Autodesk Fusion 360 part; units mm, degrees
(part 3 of 3)
sketch "草图6 (16)" plane through (0, 0, 148) normal (0, 0, 1) x (1, 0, 0) in component "19_CPU_LONGITUDINAL_BOARD_RAIL_243_84mm"
  circle A0 centre (298.45, 6.35) radius 4
extrude "Board hole 9 unchanged" add sketch "草图6 (16)" along normal blind 10 bodies 35 in component "19_CPU_LONGITUDINAL_BOARD_RAIL_243_84mm"
ref_plane "工作平面7" through (0, 0, 153.1) normal (0, 0, 1) x (1, 0, 0) in component "19_CPU_LONGITUDINAL_BOARD_RAIL_243_84mm"
sketch "草图7 (13)" plane through (0, 0, 153.1) normal (0, 0, 1) x (1, 0, 0) in component "19_CPU_LONGITUDINAL_BOARD_RAIL_243_84mm"
  circle A0 centre (298.45, 6.35) radius 2.35
extrude "Trial M3 H4.5 OD5 board insert 9" cut sketch "草图7 (13)" along normal blind 4.9 bodies 35 in component "19_CPU_LONGITUDINAL_BOARD_RAIL_243_84mm"
ref_plane "工作平面8" through (0, 0, 140) normal (0, 0, 1) x (1, 0, 0) in component "19_CPU_LONGITUDINAL_BOARD_RAIL_243_84mm"
sketch "草图8 (11)" plane through (0, 0, 140) normal (0, 0, 1) x (1, 0, 0) in component "19_CPU_LONGITUDINAL_BOARD_RAIL_243_84mm"
  circle A0 centre (294, 20) radius 1.7
extrude "M3 side rail mounting clearance'" cut sketch "草图8 (11)" along normal blind 8 bodies 35 in component "19_CPU_LONGITUDINAL_BOARD_RAIL_243_84mm"
ref_plane "工作平面5" through (0, 0, 133.5) normal (0, 0, 1) x (1, 0, 0) in component "16_CPU_VERTICAL_SIDE_FLUSH_TO_BEAM"
sketch "草图5 (20)" plane through (0, 0, 133.5) normal (0, 0, 1) x (1, 0, 0) in component "16_CPU_VERTICAL_SIDE_FLUSH_TO_BEAM"
  circle A0 centre (294, 20) radius 2.35
extrude "Trial short insert for side rail anchor'" cut sketch "草图5 (20)" along normal blind 6.5 bodies 29 in component "16_CPU_VERTICAL_SIDE_FLUSH_TO_BEAM"
ref_plane "工作平面9" through (0, 0, 140) normal (0, 0, 1) x (1, 0, 0) in component "19_CPU_LONGITUDINAL_BOARD_RAIL_243_84mm"
sketch "草图9 (9)" plane through (0, 0, 140) normal (0, 0, 1) x (1, 0, 0) in component "19_CPU_LONGITUDINAL_BOARD_RAIL_243_84mm"
  circle A0 centre (294, 225) radius 1.7
extrude "M3 side rail mounting clearance (1)'" cut sketch "草图9 (9)" along normal blind 8 bodies 35 in component "19_CPU_LONGITUDINAL_BOARD_RAIL_243_84mm"
ref_plane "工作平面6" through (0, 0, 133.5) normal (0, 0, 1) x (1, 0, 0) in component "16_CPU_VERTICAL_SIDE_FLUSH_TO_BEAM"
sketch "草图6 (17)" plane through (0, 0, 133.5) normal (0, 0, 1) x (1, 0, 0) in component "16_CPU_VERTICAL_SIDE_FLUSH_TO_BEAM"
  circle A0 centre (294, 225) radius 2.35
extrude "Trial short insert for side rail anchor (1)'" cut sketch "草图6 (17)" along normal blind 6.5 bodies 29 in component "16_CPU_VERTICAL_SIDE_FLUSH_TO_BEAM"
ref_plane "工作平面1" through (0, 0, 148) normal (0, 0, 1) x (1, 0, 0) in component "20_GPU_INDEPENDENT_FAN_SHOE_140mm"
sketch "草图1 (32)" plane through (0, 0, 148) normal (0, 0, 1) x (1, 0, 0) in component "20_GPU_INDEPENDENT_FAN_SHOE_140mm"
  line L0 (12.4, -25) -> (152.4, -25)
  line L1 (152.4, -25) -> (152.4, -19)
  line L2 (152.4, -19) -> (12.4, -19)
  line L3 (12.4, -19) -> (12.4, -25)
extrude "140 mm fan shoe" add sketch "草图1 (32)" along normal blind 12 separate body makes body 36 in component "20_GPU_INDEPENDENT_FAN_SHOE_140mm"
ref_plane "工作平面2" through (0, 0, 140) normal (0, 0, 1) x (1, 0, 0) in component "20_GPU_INDEPENDENT_FAN_SHOE_140mm"
sketch "草图2 (23)" plane through (0, 0, 140) normal (0, 0, 1) x (1, 0, 0) in component "20_GPU_INDEPENDENT_FAN_SHOE_140mm"
  line L0 (45, -19) -> (55, -19)
  line L1 (55, -19) -> (55, 6)
  line L2 (55, 6) -> (45, 6)
  line L3 (45, 6) -> (45, -19)
extrude "Deep short arm bears on front frame" add sketch "草图2 (23)" along normal blind 14 bodies 36 in component "20_GPU_INDEPENDENT_FAN_SHOE_140mm"
ref_plane "工作平面3" through (0, 0, 140) normal (0, 0, 1) x (1, 0, 0) in component "20_GPU_INDEPENDENT_FAN_SHOE_140mm"
sketch "草图3 (22)" plane through (0, 0, 140) normal (0, 0, 1) x (1, 0, 0) in component "20_GPU_INDEPENDENT_FAN_SHOE_140mm"
  circle A0 centre (50, 2) radius 1.7
extrude "M3 shoe mounting screw clearance" cut sketch "草图3 (22)" along normal blind 14 bodies 36 in component "20_GPU_INDEPENDENT_FAN_SHOE_140mm"
ref_plane "工作平面7" through (0, 0, 133.5) normal (0, 0, 1) x (1, 0, 0) in component "12_front_PCI_SUPPORT_FRAME"
sketch "草图7 (14)" plane through (0, 0, 133.5) normal (0, 0, 1) x (1, 0, 0) in component "12_front_PCI_SUPPORT_FRAME"
  circle A0 centre (50, 2) radius 2.35
extrude "Trial short insert for fan shoe anchor" cut sketch "草图7 (14)" along normal blind 6.5 bodies 24 in component "12_front_PCI_SUPPORT_FRAME"
ref_plane "工作平面4" through (0, 0, 140) normal (0, 0, 1) x (1, 0, 0) in component "20_GPU_INDEPENDENT_FAN_SHOE_140mm"
sketch "草图4 (22)" plane through (0, 0, 140) normal (0, 0, 1) x (1, 0, 0) in component "20_GPU_INDEPENDENT_FAN_SHOE_140mm"
  line L0 (105, -19) -> (115, -19)
  line L1 (115, -19) -> (115, 6)
  line L2 (115, 6) -> (105, 6)
  line L3 (105, 6) -> (105, -19)
extrude "Deep short arm bears on front frame (1)" add sketch "草图4 (22)" along normal blind 14 bodies 36 in component "20_GPU_INDEPENDENT_FAN_SHOE_140mm"
ref_plane "工作平面5" through (0, 0, 140) normal (0, 0, 1) x (1, 0, 0) in component "20_GPU_INDEPENDENT_FAN_SHOE_140mm"
sketch "草图5 (21)" plane through (0, 0, 140) normal (0, 0, 1) x (1, 0, 0) in component "20_GPU_INDEPENDENT_FAN_SHOE_140mm"
  circle A0 centre (110, 2) radius 1.7
extrude "M3 shoe mounting screw clearance (1)" cut sketch "草图5 (21)" along normal blind 14 bodies 36 in component "20_GPU_INDEPENDENT_FAN_SHOE_140mm"
ref_plane "工作平面8" through (0, 0, 133.5) normal (0, 0, 1) x (1, 0, 0) in component "12_front_PCI_SUPPORT_FRAME"
sketch "草图8 (12)" plane through (0, 0, 133.5) normal (0, 0, 1) x (1, 0, 0) in component "12_front_PCI_SUPPORT_FRAME"
  circle A0 centre (110, 2) radius 2.35
extrude "Trial short insert for fan shoe anchor (1)" cut sketch "草图8 (12)" along normal blind 6.5 bodies 24 in component "12_front_PCI_SUPPORT_FRAME"
ref_plane "工作平面1" through (0, 0, 148) normal (0, 0, 1) x (1, 0, 0) in component "20_CPU_INDEPENDENT_FAN_SHOE_140mm"
sketch "草图1 (33)" plane through (0, 0, 148) normal (0, 0, 1) x (1, 0, 0) in component "20_CPU_INDEPENDENT_FAN_SHOE_140mm"
  line L0 (156.4, -25) -> (296.4, -25)
  line L1 (296.4, -25) -> (296.4, -19)
  line L2 (296.4, -19) -> (156.4, -19)
  line L3 (156.4, -19) -> (156.4, -25)
extrude "140 mm fan shoe'" add sketch "草图1 (33)" along normal blind 12 separate body makes body 37 in component "20_CPU_INDEPENDENT_FAN_SHOE_140mm"
ref_plane "工作平面2" through (0, 0, 140) normal (0, 0, 1) x (1, 0, 0) in component "20_CPU_INDEPENDENT_FAN_SHOE_140mm"
sketch "草图2 (24)" plane through (0, 0, 140) normal (0, 0, 1) x (1, 0, 0) in component "20_CPU_INDEPENDENT_FAN_SHOE_140mm"
  line L0 (195, -19) -> (205, -19)
  line L1 (205, -19) -> (205, 6)
  line L2 (205, 6) -> (195, 6)
  line L3 (195, 6) -> (195, -19)
extrude "Deep short arm bears on front frame'" add sketch "草图2 (24)" along normal blind 14 bodies 37 in component "20_CPU_INDEPENDENT_FAN_SHOE_140mm"
ref_plane "工作平面3" through (0, 0, 140) normal (0, 0, 1) x (1, 0, 0) in component "20_CPU_INDEPENDENT_FAN_SHOE_140mm"
sketch "草图3 (23)" plane through (0, 0, 140) normal (0, 0, 1) x (1, 0, 0) in component "20_CPU_INDEPENDENT_FAN_SHOE_140mm"
  circle A0 centre (200, 2) radius 1.7
extrude "M3 shoe mounting screw clearance'" cut sketch "草图3 (23)" along normal blind 14 bodies 37 in component "20_CPU_INDEPENDENT_FAN_SHOE_140mm"
ref_plane "工作平面6" through (0, 0, 133.5) normal (0, 0, 1) x (1, 0, 0) in component "12_front_CPU_SUPPORT_FRAME"
sketch "草图6 (18)" plane through (0, 0, 133.5) normal (0, 0, 1) x (1, 0, 0) in component "12_front_CPU_SUPPORT_FRAME"
  circle A0 centre (200, 2) radius 2.35
extrude "Trial short insert for fan shoe anchor'" cut sketch "草图6 (18)" along normal blind 6.5 bodies 25 in component "12_front_CPU_SUPPORT_FRAME"
ref_plane "工作平面4" through (0, 0, 140) normal (0, 0, 1) x (1, 0, 0) in component "20_CPU_INDEPENDENT_FAN_SHOE_140mm"
sketch "草图4 (23)" plane through (0, 0, 140) normal (0, 0, 1) x (1, 0, 0) in component "20_CPU_INDEPENDENT_FAN_SHOE_140mm"
  line L0 (260, -19) -> (270, -19)
  line L1 (270, -19) -> (270, 6)
  line L2 (270, 6) -> (260, 6)
  line L3 (260, 6) -> (260, -19)
extrude "Deep short arm bears on front frame (1)'" add sketch "草图4 (23)" along normal blind 14 bodies 37 in component "20_CPU_INDEPENDENT_FAN_SHOE_140mm"
ref_plane "工作平面5" through (0, 0, 140) normal (0, 0, 1) x (1, 0, 0) in component "20_CPU_INDEPENDENT_FAN_SHOE_140mm"
sketch "草图5 (22)" plane through (0, 0, 140) normal (0, 0, 1) x (1, 0, 0) in component "20_CPU_INDEPENDENT_FAN_SHOE_140mm"
  circle A0 centre (265, 2) radius 1.7
extrude "M3 shoe mounting screw clearance (1)'" cut sketch "草图5 (22)" along normal blind 14 bodies 37 in component "20_CPU_INDEPENDENT_FAN_SHOE_140mm"
ref_plane "工作平面7" through (0, 0, 133.5) normal (0, 0, 1) x (1, 0, 0) in component "12_front_CPU_SUPPORT_FRAME"
sketch "草图7 (15)" plane through (0, 0, 133.5) normal (0, 0, 1) x (1, 0, 0) in component "12_front_CPU_SUPPORT_FRAME"
  circle A0 centre (265, 2) radius 2.35
extrude "Trial short insert for fan shoe anchor (1)'" cut sketch "草图7 (15)" along normal blind 6.5 bodies 25 in component "12_front_CPU_SUPPORT_FRAME"
ref_plane "工作平面15" through (0, 0, 127.9) normal (0, 0, 1) x (1, 0, 0) in component "18_REAR_BEAM_PCI_TAPERED_END_AND_FRONT_LAP"
sketch "草图15 (3)" plane through (0, 0, 127.9) normal (0, 0, 1) x (1, 0, 0) in component "18_REAR_BEAM_PCI_TAPERED_END_AND_FRONT_LAP"
  line L0 (136.77, 218.5) -> (145.17, 218.5)
  line L1 (145.17, 218.5) -> (145.17, 237.84)
  line L2 (145.17, 237.84) -> (136.77, 237.84)
  line L3 (136.77, 237.84) -> (136.77, 218.5)
extrude "Clearance channel for continuous middle rail rib" cut sketch "草图15 (3)" along normal blind 12.2 bodies 31 in component "18_REAR_BEAM_PCI_TAPERED_END_AND_FRONT_LAP"
ref_plane "工作平面16" through (0, 0, 133.5) normal (0, 0, 1) x (1, 0, 0) in component "18_REAR_BEAM_PCI_TAPERED_END_AND_FRONT_LAP"
sketch "草图16 (3)" plane through (0, 0, 133.5) normal (0, 0, 1) x (1, 0, 0) in component "18_REAR_BEAM_PCI_TAPERED_END_AND_FRONT_LAP"
  circle A0 centre (134, 222.5) radius 2.35
extrude "Trial short M3 insert for centre rail rear anchor" cut sketch "草图16 (3)" along normal blind 6.5 bodies 31 in component "18_REAR_BEAM_PCI_TAPERED_END_AND_FRONT_LAP"
ref_plane "工作平面12" through (0, 0, 128) normal (0, 0, 1) x (1, 0, 0) in component "19_MID_LONGITUDINAL_BOARD_RAIL_243_84mm"
sketch "草图12 (4)" plane through (0, 0, 128) normal (0, 0, 1) x (1, 0, 0) in component "19_MID_LONGITUDINAL_BOARD_RAIL_243_84mm"
  line L0 (136.97, 218.5) -> (144.97, 218.5)
  line L1 (144.97, 218.5) -> (144.97, 237.84)
  line L2 (144.97, 237.84) -> (136.97, 237.84)
  line L3 (136.97, 237.84) -> (136.97, 218.5)
extrude "Continue underside rib nearly to rail end" add sketch "草图12 (4)" along normal blind 12 bodies 34 in component "19_MID_LONGITUDINAL_BOARD_RAIL_243_84mm"
ref_plane "工作平面13" through (0, -218.5, 0) normal (0, 1, 0) x (0, 0, 1) in component "19_MID_LONGITUDINAL_BOARD_RAIL_243_84mm"
sketch "草图13 (4)" plane through (0, -218.5, 0) normal (0, 1, 0) x (1, 0, 0) in component "19_MID_LONGITUDINAL_BOARD_RAIL_243_84mm"
  line L0 (136.97, -134, 437) -> (144.97, -134, 437)
  line L1 (144.97, -134, 437) -> (149.97, -140, 437)
  line L2 (149.97, -140, 437) -> (131.97, -140, 437)
  line L3 (131.97, -140, 437) -> (136.97, -134, 437)
ref_plane "工作平面14" through (0, 0, 140) normal (0, 0, 1) x (1, 0, 0) in component "19_MID_LONGITUDINAL_BOARD_RAIL_243_84mm"
sketch "草图14 (4)" plane through (0, 0, 140) normal (0, 0, 1) x (1, 0, 0) in component "19_MID_LONGITUDINAL_BOARD_RAIL_243_84mm"
  circle A0 centre (134, 222.5) radius 1.7
extrude "Centre rail rear seat mounting clearance" cut sketch "草图14 (4)" along normal blind 8 bodies 34 in component "19_MID_LONGITUDINAL_BOARD_RAIL_243_84mm"
component "10_GPU_140_FAN_MOUNT" placed x (1, 0, 0) y (0, 1, 0) z (0, 0, 1) at (0, 0, -50)
component "10_CPU_140_FAN_MOUNT" placed x (1, 0, 0) y (0, 1, 0) z (0, 0, 1) at (0, 0, -50)
component "REF_CASE_FAN_GPU_140x140x25" placed x (1, 0, 0) y (0, 1, 0) z (0, 0, 1) at (0, 0, -50)
component "REF_AIRFLOW_GPU_FRONT_TO_REAR" placed x (1, 0, 0) y (0, 1, 0) z (0, 0, 1) at (0, 0, -50)
component "REF_CASE_FAN_CPU_140x140x25" placed x (1, 0, 0) y (0, 1, 0) z (0, 0, 1) at (0, 0, -50)
component "REF_AIRFLOW_CPU_FRONT_TO_REAR" placed x (1, 0, 0) y (0, 1, 0) z (0, 0, 1) at (0, 0, -50)
component "REF_BOARD_304.8x243.84_NUMBERED_HOLES" placed x (1, 0, 0) y (0, 1, 0) z (0, 0, 1) at (0, 0, -50)
component "REF_CPU_RIGHT" placed x (1, 0, 0) y (0, 1, 0) z (0, 0, 1) at (0, 0, -50)
component "REF_MEMORY_RIGHT_FRONT" placed x (1, 0, 0) y (0, 1, 0) z (0, 0, 1) at (0, 0, -50)
component "REF_PRIMARY_PCIE_X126.4_APPROX" placed x (1, 0, 0) y (0, 1, 0) z (0, 0, 1) at (0, 0, -50)
component "REF_SECOND_LONG_PCIE_X60_APPROX" placed x (1, 0, 0) y (0, 1, 0) z (0, 0, 1) at (0, 0, -50)
component "REF_GPU_FANS_TO_MINUS_X" placed x (1, 0, 0) y (0, 1, 0) z (0, 0, 1) at (0, 0, -50)
component "REF_GPU_FAN_MARKERS_MINUS_X" placed x (1, 0, 0) y (0, 1, 0) z (0, 0, 1) at (0, 0, -50)
component "04_front_GROUND_BAR_290mm_FLAT_PSU" placed x (1, 0, 0) y (0, 1, 0) z (0, 0, 1) at (0, 0, 0)
component "04_rear_GROUND_BAR_290mm_FLAT_PSU" placed x (1, 0, 0) y (0, 1, 0) z (0, 0, 1) at (0, 0, 0)
component "05_CENTERED_FLAT_PSU_CRADLE_OPEN_INTAKE" placed x (1, 0, 0) y (0, 1, 0) z (0, 0, 1) at (0, 0, 0)
component "REF_PSU_FLAT_CENTERED_150x140x86" placed x (1, 0, 0) y (0, 1, 0) z (0, 0, 1) at (0, 0, 0)
component "REF_PSU_INTAKE_DOWN_MINUS_Z" placed x (1, 0, 0) y (0, 1, 0) z (0, 0, 1) at (0, 0, 0)
component "REF_PSU_REAR_EXHAUST_PLUS_Y" placed x (1, 0, 0) y (0, 1, 0) z (0, 0, 1) at (0, 0, 0)
component "12_front_PCI_SUPPORT_FRAME" placed x (1, 0, 0) y (0, 1, 0) z (0, 0, 1) at (0, 0, 0)
component "12_front_CPU_SUPPORT_FRAME" placed x (1, 0, 0) y (0, 1, 0) z (0, 0, 1) at (0, 0, 0)
component "07_GPU_REINFORCED_REAR_TOWER" placed x (1, 0, 0) y (0, 1, 0) z (0, 0, 1) at (0, 0, 0)
component "08_GPU_UPPER_EAR_LEDGE_ADJUSTABLE" placed x (1, 0, 0) y (0, 1, 0) z (0, 0, 1) at (0, 0, 0)
component "08_GPU_LOWER_TWO_TAB_RECEIVER_ADJUSTABLE" placed x (1, 0, 0) y (0, 1, 0) z (0, 0, 1) at (0, 0, 0)
component "16_CPU_VERTICAL_SIDE_FLUSH_TO_BEAM" placed x (1, 0, 0) y (0, 1, 0) z (0, 0, 1) at (0, 0, 0)
component "16_PCI_INSET_SIDE_16_45mm" placed x (1, 0, 0) y (0, 1, 0) z (0, 0, 1) at (0, 0, 0)
component "18_REAR_BEAM_PCI_TAPERED_END_AND_FRONT_LAP" placed x (1, 0, 0) y (0, 1, 0) z (0, 0, 1) at (0, 0, 0)
component "18_REAR_BEAM_CPU_END_AND_REAR_LAP" placed x (1, 0, 0) y (0, 1, 0) z (0, 0, 1) at (0, 0, 0)
component "19_PCI_LONGITUDINAL_BOARD_RAIL_243_84mm" placed x (1, 0, 0) y (0, 1, 0) z (0, 0, 1) at (0, 0, 0)
component "19_MID_LONGITUDINAL_BOARD_RAIL_243_84mm" placed x (1, 0, 0) y (0, 1, 0) z (0, 0, 1) at (0, 0, 0)
component "19_CPU_LONGITUDINAL_BOARD_RAIL_243_84mm" placed x (1, 0, 0) y (0, 1, 0) z (0, 0, 1) at (0, 0, 0)
component "20_GPU_INDEPENDENT_FAN_SHOE_140mm" placed x (1, 0, 0) y (0, 1, 0) z (0, 0, 1) at (0, 0, 0)
component "20_CPU_INDEPENDENT_FAN_SHOE_140mm" placed x (1, 0, 0) y (0, 1, 0) z (0, 0, 1) at (0, 0, 0)
equation "desk_limit = 290 mm" comment "V03 layout review; fixed profiles require regeneration"
equation "footprint_width = 290 mm" comment "V03 layout review; fixed profiles require regeneration"
equation "board_width = 304.8 mm" comment "V03 layout review; fixed profiles require regeneration"
equation "board_depth = 243.84 mm" comment "V03 layout review; fixed profiles require regeneration"
equation "board_bottom_height = 208 mm" comment "V03 layout review; fixed profiles require regeneration"
equation "approx_slot_x = 126.4 mm" comment "V03 layout review; fixed profiles require regeneration"
